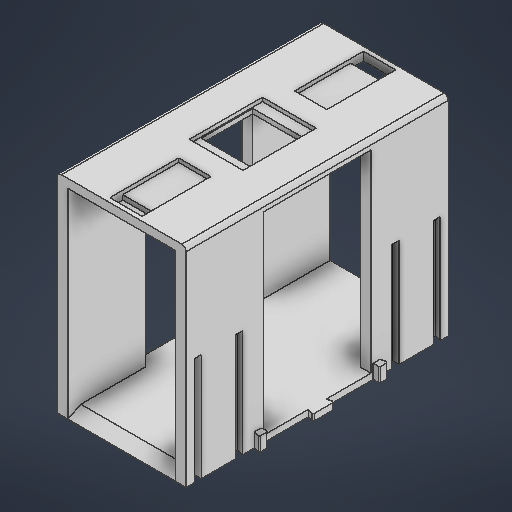
# Autodesk Inventor part: Camel Gate
Saved by Autodesk Inventor 2026.4 (Build 304435000, 435)
## iProperties
Created: 2026-10-05
Part Number: Camel Gate
Material: Generic
Document SubType Name: Modeling
Designer: LENOVO
Density: 1 g/cm^3
Appearance: Default
Author: LENOVO
Autodesk Inventor part; units mm, degrees
ref_plane "YZ Plane" through (0, 0, 0) normal (1, 0, 0) x (0, 1, 0)
ref_plane "XZ Plane" through (0, 0, 0) normal (0, 1, 0) x (-1, 0, 0)
ref_plane "XY Plane" through (0, 0, 0) normal (0, 0, 1) x (1, 0, 0)
sketch "Sketch1" plane through (0, 0, 0) normal (0, 1, 0) x (-1, 0, 0)
  line L0 (-30, 25) -> (30, 25)
  line L1 (30, 25) -> (30, -25)
  line L2 (30, -25) -> (-30, -25)
  line L3 (-30, -25) -> (-30, 25)
  line L4 (-30, 25) -> (30, -25) construction
  line L5 (30, 25) -> (-30, -25) construction
  line L6 (-30, 25) -> (30, 25)
  line L7 (30, 25) -> (30, 31)
  line L8 (30, 31) -> (-30, 31)
  line L9 (-30, 31) -> (-30, 25)
  point P0 (0, 0)
  dimension "d0" = 60
  dimension "d1" = 50
  dimension "d2" = 6
  constraints: 20 end point, 4 parallel, 2 horizontal, 2 midpoint, 2 perpendicular
  measures "d0" distance of L1.end L2.end
  measures "d1" distance of L0.end L1.end
  measures "d2" distance of L7.end L6.end
extrude "Extrusion1" add sketch "Sketch1" along normal blind 3 contours L0 L1 L2 L3
sketch "Sketch2" plane through (0, 3, 0) normal (0, 1, 0) x (1, 0, 0)
  line L0 (30, 25) -> (-30, 25) projected
  line L1 (-30, 25) -> (-30, -25) projected
  line L2 (-30, -25) -> (30, -25) projected
  line L3 (30, -25) -> (30, 25) projected
  line L4 (30, -25) -> (-30, -25)
  line L5 (-30, -25) -> (-30, -31)
  line L6 (-30, -31) -> (30, -31)
  line L7 (30, -31) -> (30, -25)
  line L8 (30, 25) -> (-30, 25)
  line L9 (-30, 25) -> (-30, 31)
  line L10 (-30, 31) -> (30, 31)
  line L11 (30, 31) -> (30, 25)
  point P0 (0, 0)
  dimension "d5" = 6
  dimension "d6" = 6
  constraints: 16 end point, 4 parallel, 2 horizontal, 2 perpendicular, 1 point on line
  measures "d5" distance of L5.end L4.end
  measures "d6" distance of L8.end L9.end
extrude "Extrusion2" add sketch "Sketch2" along normal blind 4 and the other way blind 3 contours L0 L9 L10 L11 | L7 L6 L5 L2
sketch "Sketch3" plane through (0, 0, 0) normal (0, -1, 0) x (1, 0, 0)
  line L0 (30, -31) -> (30, 31)
  line L1 (30, -29.1962) -> (30, -31)
  line L2 (30, -4.1962) -> (30, -26)
  line L3 (33, -26) -> (33, -30)
  line L4 (33, -30) -> (30, -29.1962)
  line L5 (30, -26) -> (33, -26)
  line L6 (30, 26) -> (30, 4.1962)
  line L7 (33, 5) -> (33, -5)
  line L8 (33, -5) -> (30, -4.1962)
  line L9 (30, 4.1962) -> (33, 5)
  line L10 (33, 30) -> (33, 26)
  line L11 (33, 26) -> (30, 26)
  line L12 (30, 29.1962) -> (33, 30)
  line L13 (30, 31) -> (30, 29.1962)
  line L14 (27, 30) -> (27, 26)
  line L15 (30, 29.1962) -> (27, 30)
  line L16 (27, 26) -> (30, 26)
  line L17 (30, -26) -> (27, -26)
  line L18 (27, -26) -> (27, -30)
  line L19 (27, -30) -> (30, -29.1962)
  line L20 (27, 5) -> (27, -5)
  line L21 (27, -5) -> (30, -4.1962)
  line L22 (30, 4.1962) -> (27, 5)
  line L23 (30, -31) -> (30, 31) projected
  line L24 (30, 31) -> (-30, 31) projected
  line L25 (-30, 31) -> (-30, -31) projected
  line L26 (-30, -31) -> (30, -31) projected
  point P0 (-156.1261, 8.1941)
  point P1 (-156.1261, 11.3903)
  point P2 (-156.1261, 33.1941)
  point P3 (-156.1261, 41.5864)
  point P4 (-156.1261, 63.3903)
  point P5 (-156.1261, 66.5864)
  point P6 (118.8522, -16.7785)
  point P7 (118.8522, -13.5824)
  point P8 (118.8522, 8.2215)
  point P9 (118.8522, 16.6138)
  point P10 (118.8522, 38.4176)
  point P11 (118.8522, 41.6138)
  point P12 (30, -26)
  constraints: 46 end point, 6 symmetric about line
extrude "Extrusion3" add sketch "Sketch3" against normal blind 3 contours L0 L5 L3 L4 | L0 L9 L7 L8 | L12 L10 L11 L0
sketch "Sketch4" plane through (0, 0, 0) normal (0, -1, 0) x (1, 0, 0)
  line L0 (30, -31) -> (30, -29.1962) projected
  line L1 (30, -29.1962) -> (33, -30) projected
  line L2 (33, -30) -> (33, -26) projected
  line L3 (33, -26) -> (30, -26) projected
  line L4 (30, -26) -> (30, -4.1962) projected
  line L5 (30, -4.1962) -> (33, -5) projected
  line L6 (33, -5) -> (33, 5) projected
  line L7 (33, 5) -> (30, 4.1962) projected
  line L8 (30, 4.1962) -> (30, 26) projected
  line L9 (30, 26) -> (33, 26) projected
  line L10 (33, 26) -> (33, 30) projected
  line L11 (33, 30) -> (30, 29.1962) projected
  line L12 (30, 29.1962) -> (30, 31) projected
  line L13 (30, 31) -> (-30, 31) projected
  line L14 (-30, 31) -> (-30, -31) projected
  line L15 (-30, -31) -> (30, -31) projected
  line L16 (0, 31) -> (0, -31)
  line L17 (-30, -31) -> (-30, -29.1962)
  line L18 (-30, -29.1962) -> (-33, -30)
  line L19 (-33, -30) -> (-33, -26)
  line L20 (-33, -26) -> (-30, -26)
  line L21 (-30, -26) -> (-30, -4.1962)
  line L22 (-30, -4.1962) -> (-33, -5)
  line L23 (-33, -5) -> (-33, 5)
  line L24 (-33, 5) -> (-30, 4.1962)
  line L25 (-30, 4.1962) -> (-30, 26)
  line L26 (-30, 26) -> (-33, 26)
  line L27 (-33, 26) -> (-33, 30)
  line L28 (-33, 30) -> (-30, 29.1962)
  line L29 (-30, 29.1962) -> (-30, 31)
  line L30 (-30, -4.1962) -> (-27, -5)
  line L31 (-27, -5) -> (-27, 5)
  line L32 (-27, 5) -> (-30, 4.1962)
  line L33 (-30, 26) -> (-27, 26)
  line L34 (-27, -26) -> (-30, -26)
  line L35 (-30, -29.1962) -> (-27, -30)
  line L36 (-27, -30) -> (-27, -26)
  line L37 (-27, 30) -> (-30, 29.1962)
  line L38 (-27, 26) -> (-27, 30)
  point P0 (0, 0)
  constraints: 46 end point, 18 symmetric about line, 2 midpoint
extrude "Extrusion4" cut sketch "Sketch4" against normal blind 3 contours L14 L34 L36 L35 | L37 L38 L33 L14 | L14 L32 L31 L30
sketch "Sketch5" plane through (0, 3, 0) normal (0, -1, 0) x (1, 0, 0)
  line L0 (-30, -26) -> (-27, -26) projected
  line L1 (-30, -29.1962) -> (-30, -26) projected
  line L2 (-27, -30) -> (-30, -29.1962) projected
  line L3 (-27, -26) -> (-27, -30) projected
  line L4 (-30, 29.1962) -> (-27, 30) projected
  line L5 (-30, 26) -> (-30, 29.1962) projected
  line L6 (-27, 26) -> (-30, 26) projected
  line L7 (-27, 30) -> (-27, 26) projected
  point P0 (0, 0)
extrude "Extrusion5" cut sketch "Sketch5" against normal blind 3.5
sketch "Sketch6" plane through (0, 3, 0) normal (0, 1, 0) x (1, 0, 0)
  line L0 (30, -29.1962) -> (33, -30) projected
  line L1 (33, -30) -> (33, -26) projected
  line L2 (33, -26) -> (30, -26) projected
  line L3 (30, -29.1962) -> (30, -26) projected
  line L4 (30, 26) -> (33, 26) projected
  line L5 (33, 26) -> (33, 30) projected
  line L6 (33, 30) -> (30, 29.1962) projected
  line L7 (30, 26) -> (30, 29.1962) projected
  point P0 (0, 0)
extrude "Extrusion6" add sketch "Sketch6" along normal blind 3.5
fillet "Fillet1" radius 0.5 6 edges at (33, 3.25, 26) (33, 3.25, 30) (33, 1.5, 5) (33, 1.5, -5) (33, 3.25, -26) (33, 3.25, -30)
fillet "Fillet2" radius 0.5 6 edges at (-30, 3.25, -26) (-30, 3.25, -29.1962) (-30, 1.5, 4.1962) (-30, 1.5, -4.1962) (-30, 3.25, 29.1962) (-30, 3.25, 26)
sketch "Sketch7" plane through (-30, 0, 31) normal (-1, 0, 0) x (0, 0, 1)
  line L0 (-5.5, 6.5) -> (-5.5, 0) projected
  line L1 (-5.5, 6.5) -> (-1.1522, 6.5) projected
  line L2 (-1.1522, 0) -> (-1.1522, 6.5) projected
  line L3 (0, 0) -> (-1.1522, 0) projected
  line L4 (0, 0) -> (0, 7) projected
  line L5 (-6, 7) -> (0, 7) projected
  line L6 (-6, 3) -> (-6, 7) projected
  line L7 (-26.1522, 3) -> (-6, 3) projected
  line L8 (-26.1522, 0) -> (-26.1522, 3) projected
  line L9 (-5.5, 0) -> (-26.1522, 0) projected
  line L10 (-35.8478, 3) -> (-35.8478, 0) projected
  line L11 (-56, 3) -> (-35.8478, 3) projected
  line L12 (-56, 3) -> (-56, 7) projected
  line L13 (-62, 7) -> (-56, 7) projected
  line L14 (-62, 0) -> (-62, 7) projected
  line L15 (-60.8478, 0) -> (-62, 0) projected
  line L16 (-60.8478, 6.5) -> (-60.8478, 0) projected
  line L17 (-60.8478, 6.5) -> (-56.5, 6.5) projected
  line L18 (-56.5, 0) -> (-56.5, 6.5) projected
  line L19 (-35.8478, 0) -> (-56.5, 0) projected
  line L20 (-56, 3) -> (-6, 3)
  line L21 (-6, 3) -> (-6, 93)
  line L22 (-6, 93) -> (-56, 93)
  line L23 (-56, 93) -> (-56, 3)
  line L24 (-62, 7) -> (0, 7)
  line L25 (0, 7) -> (0, 97)
  line L26 (0, 97) -> (-62, 97)
  line L27 (-62, 97) -> (-62, 7)
  point P0 (-31, 0)
  dimension "d21" = 90
  dimension "d22" = 90
  constraints: 16 end point, 4 parallel, 2 horizontal, 2 perpendicular
  measures "d21" distance of L21.end L20.end
  measures "d22" distance of L25.end L24.end
extrude "Extrusion7" add sketch "Sketch7" against normal blind 60 contours L5 L21 L22 L23 L13 L27 L26 L25
sketch "Sketch8" plane through (-30, 0, 31) normal (0, 0, 1) x (1, 0, 0)
  line L0 (60, 3) -> (0, 3) projected
  line L1 (60, 3) -> (60, 93) projected
  line L2 (0, 93) -> (60, 93) projected
  line L3 (0, 3) -> (0, 93) projected
  line L4 (0, 3) -> (60, 3) projected
  line L5 (60, 0) -> (0, 0) projected
  line L6 (5, 3) -> (55, 3)
  line L7 (55, 3) -> (55, 93)
  line L8 (55, 93) -> (5, 93)
  line L9 (5, 93) -> (5, 3)
  point P0 (30, 0)
  point P1 (30, 0)
  point P2 (5, 93)
  dimension "d25" = 25
  dimension "d26" = 50
  dimension "d27" = 90
  constraints: 8 end point, 2 parallel, 1 horizontal, 1 midpoint, 1 perpendicular, 1 point on line
  measures "d25" horizontal distance of L6.start point (30, 0)
  measures "d26" distance of L8.end L7.end
  measures "d27" distance of L7.end L6.end
extrude "Extrusion8" cut sketch "Sketch8" against normal blind 62 contours L0 L9 L2 L7
sketch "Sketch9" plane through (-30, 97, 31) normal (0, 1, 0) x (1, 0, 0)
  line L0 (42, 43) -> (18, 43)
  line L1 (18, 43) -> (18, 19)
  line L2 (18, 19) -> (42, 19)
  line L3 (42, 19) -> (42, 43)
  line L4 (42, 43) -> (18, 19) construction
  line L5 (18, 43) -> (42, 19) construction
  point P0 (30, 31)
  dimension "d30" = 24
  dimension "d31" = 24
  constraints: 12 end point, 2 midpoint, 2 parallel, 1 horizontal, 1 perpendicular
  measures "d30" distance of L2.end L1.end
  measures "d31" distance of L1.end L0.end
extrude "Extrusion9" cut sketch "Sketch9" against normal blind 5
sketch "Sketch10" plane through (-30, 97, 31) normal (0, 1, 0) x (1, 0, 0)
  line L0 (42.5, 48) -> (17.5, 48)
  line L1 (17.5, 48) -> (17.5, 14)
  line L2 (17.5, 14) -> (42.5, 14)
  line L3 (42.5, 14) -> (42.5, 48)
  line L4 (42.5, 48) -> (17.5, 14) construction
  line L5 (17.5, 48) -> (42.5, 14) construction
  point P0 (30, 31)
  dimension "d34" = 25
  dimension "d35" = 34
  constraints: 12 end point, 2 midpoint, 2 parallel, 1 horizontal, 1 perpendicular
  measures "d34" distance of L2.end L1.end
  measures "d35" distance of L1.end L0.end
extrude "Extrusion10" cut sketch "Sketch10" against normal blind 1.8
sketch "Sketch11" plane through (-30, 0, 31) normal (0, 0, 1) x (1, 0, 0)
  line L0 (55, 93) -> (55, 3) projected
  line L1 (55, 3) -> (5, 3) projected
  line L2 (5, 3) -> (5, 93) projected
  line L3 (5, 93) -> (55, 93) projected
  line L4 (60, 0) -> (60, 97) projected
  line L5 (0, 97) -> (60, 97) projected
  line L6 (0, 0) -> (0, 97) projected
  line L7 (60, 0) -> (0, 0) projected
  point P0 (30, 0)
extrude "Extrusion11" add sketch "Sketch11" along normal blind 30
sketch "Sketch12" plane through (-30, 97, -31) normal (0, 1, 0) x (1, 0, 0)
  line L0 (42.5, -48) -> (17.5, -48) projected
  line L1 (17.5, -48) -> (17.5, -14) projected
  line L2 (17.5, -14) -> (42.5, -14) projected
  line L3 (42.5, -14) -> (42.5, -48) projected
  line L4 (0, -92) -> (0, 0) projected
  line L5 (60, -92) -> (0, -92) projected
  line L6 (60, 0) -> (60, -92) projected
  line L7 (0, 0) -> (60, 0) projected
  line L8 (22.5, -90) -> (37.5, -90)
  line L9 (37.5, -90) -> (37.5, -58)
  line L10 (37.5, -58) -> (22.5, -58)
  line L11 (22.5, -58) -> (22.5, -90)
  point P0 (30, -31)
  point P1 (30, -92)
  point P2 (22.5, -92)
  dimension "d40" = 7.5
  dimension "d41" = 2
  dimension "d42" = 15
  dimension "d43" = 32
  constraints: 8 end point, 2 parallel, 1 horizontal, 1 midpoint, 1 perpendicular, 1 point on line
  measures "d40" distance of point (30, -92) point (22.5, -92)
  measures "d41" distance from line of L5 L8.start
  measures "d42" distance of L10.end L9.end
  measures "d43" distance of L9.end L8.end
extrude "Extrusion12" cut sketch "Sketch12" against normal blind 1.8 contours L11 L10 L9 L8
sketch "Sketch13" plane through (-30, 95.2, -31) normal (0, 1, 0) x (1, 0, 0)
  line L0 (37.5, -58) -> (37.5, -90) projected
  line L1 (22.5, -58) -> (37.5, -58) projected
  line L2 (22.5, -90) -> (22.5, -58) projected
  line L3 (37.5, -90) -> (22.5, -90) projected
  line L4 (37.5, -58) -> (22.5, -58)
  line L5 (22.5, -58) -> (22.5, -64)
  line L6 (22.5, -64) -> (37.5, -64)
  line L7 (37.5, -64) -> (37.5, -58)
  line L8 (37.5, -58) -> (37.5, -90) projected
  line L9 (37.5, -90) -> (22.5, -90)
  line L10 (22.5, -90) -> (22.5, -84)
  line L11 (22.5, -84) -> (37.5, -84)
  line L12 (37.5, -84) -> (37.5, -90)
  point P0 (30, -31)
  dimension "d46" = 15
  dimension "d47" = 6
  dimension "d50" = 15
  dimension "d51" = 6
  constraints: 16 end point, 4 parallel, 2 horizontal, 2 perpendicular
  measures "d46" distance of L6.end L5.end
  measures "d47" distance of L5.end L4.end
  measures "d50" distance of L10.end L11.end
  measures "d51" distance of L9.end L10.end
extrude "Extrusion14" cut sketch "Sketch13" against normal blind 3 contours L0 L3 L2 L11
sketch "Sketch14" plane through (0, 0, 0) normal (0, -1, 0) x (1, 0, 0)
  line L0 (30, 61) -> (-30, 61) projected
  line L1 (30, -31) -> (30, 61) projected
  line L2 (-30, 61) -> (30, 61)
  line L3 (30, 61) -> (30, 31)
  line L4 (30, 31) -> (-30, 31)
  line L5 (-30, 31) -> (-30, 61)
  line L6 (27, 58) -> (33, 58)
  line L7 (33, 58) -> (33, 54)
  line L8 (33, 54) -> (27, 54)
  line L9 (27, 54) -> (27, 58)
  line L10 (27, 58) -> (33, 54) construction
  line L11 (33, 58) -> (27, 54) construction
  line L12 (30, 46) -> (-30, 46)
  line L13 (33, 58) -> (30, 57.1962)
  line L14 (33, 58) -> (36.1058, 58) construction
  line L15 (27, 58) -> (30, 57.1962)
  line L16 (27, 34) -> (33, 34)
  line L17 (33, 34) -> (33, 38)
  line L18 (33, 38) -> (27, 38)
  line L19 (27, 38) -> (27, 34)
  line L20 (27, 34) -> (33, 38) construction
  line L21 (33, 34) -> (27, 38) construction
  line L22 (33, 34) -> (30, 34.8038)
  line L23 (33, 34) -> (36.1058, 34) construction
  line L24 (27, 34) -> (30, 34.8038)
  line L25 (0, 61) -> (0, 46)
  line L26 (-30, 61) -> (-30, 31)
  line L27 (-27, 58) -> (-33, 58)
  line L28 (-33, 58) -> (-33, 54)
  line L29 (-33, 54) -> (-27, 54)
  line L30 (-27, 54) -> (-27, 58)
  line L31 (-27, 58) -> (-33, 54) construction
  line L32 (-33, 58) -> (-27, 54) construction
  line L33 (-33, 58) -> (-30, 57.1962)
  line L34 (-33, 58) -> (-36.1058, 58) construction
  line L35 (-27, 58) -> (-30, 57.1962)
  line L36 (-27, 38) -> (-27, 34)
  line L37 (-27, 34) -> (-30, 34.8038)
  line L38 (-33, 38) -> (-27, 38)
  line L39 (-27, 34) -> (-33, 38) construction
  line L40 (-27, 34) -> (-33, 34)
  line L41 (-33, 34) -> (-27, 38) construction
  line L42 (-33, 34) -> (-33, 38)
  line L43 (-33, 34) -> (-30, 34.8038)
  line L44 (-33, 34) -> (-36.1058, 34) construction
  point P0 (0, 0)
  point P1 (30, 56)
  point P2 (30, 36)
  point P3 (-30, 56)
  point P4 (-30, 36)
  point P5 (30, 54)
  point P6 (30, 38)
  point P7 (-30, 38)
  point P8 (-30, 54)
  dimension "d54" = 30
  dimension "d55" = 6
  dimension "d56" = 4
  dimension "d57" = 3
  dimension "d58" = 195
  constraints: 86 end point, 22 symmetric about line, 6 midpoint, 5 point on line, 4 parallel, 3 horizontal, 2 perpendicular, 1 equal length
  measures "d54" distance of L2.end L3.end
  measures "d55" distance of L7.end L8.end
  measures "d56" distance of L6.end L7.end
  measures "d57" distance between parallel lines of L0 L6
extrude "Extrusion15" cut sketch "Sketch14" against normal blind 50 contours L1 L8 L9 L15 | L35 L30 L29 L5 | L1 L24 L19 L18 | L38 L36 L37 L5
mirror "Mirror1" about plane through (0, 0, 0) normal (0, 0, 1) of "Extrusion11", "Extrusion12", "Extrusion14", "Extrusion15"
fillet "Fillet3" radius 2 2 edges at (30, 97, 0) (-30, 97, 0)
chamfer "Chamfer1" distance 3 distance2 6 1 edges at (0, 3, 61) measured on face at (0, 2.5, 61)
body "Solid1"
